Autodesk Fusion 360 part; units mm, degrees
(part 2 of 2)
ref_plane "Plano de trabalho2" through (0, 0, -3) normal (0, 0, 1) x (1, 0, 0) in component "09 / Bicos MIC frontais / dutos a medir"
sketch "Esboço2 (10)" plane through (0, 0, -3) normal (0, 0, 1) x (1, 0, 0) in component "09 / Bicos MIC frontais / dutos a medir"
  circle A0 centre (73, -51) radius 1.8
  circle A1 centre (73, -51) radius 1
extrude "Extrusão2" add sketch "Esboço2 (10)" against normal blind 3 separate body makes body 15 in component "09 / Bicos MIC frontais / dutos a medir"
ref_plane "Plano de trabalho3" through (-90, 0, 0) normal (1, 0, 0) x (0, 1, 0) in component "REF / Vidro 164.28 x 99.17 / area ativa assimetrica"
sketch "Esboço3 (8)" plane through (-90, 0, 0) normal (1, 0, 0) x (0, 0, -1) in component "REF / Vidro 164.28 x 99.17 / area ativa assimetrica"
  line L0 (-0.2, -58) -> (-0.2, -55.065)
  line L1 (-0.2, -55.065) -> (3.2, -53.9603)
  line L2 (3.2, -53.9603) -> (3.2, -58)
  line L3 (3.2, -58) -> (-0.2, -58)
extrude "Nivelar moldura no plano da mesa" cut sketch "Esboço3 (8)" along normal blind 180 bodies 1 in component "01 / Moldura fina / microfones frontais"
sketch "Esboço9 (2)" plane through (0, 0, 0) normal (0, 0, 1) x (1, 0, 0) in component "03 / Tampa traseira / grelha alto-falante + ventilacao"
  point P0 (-10, 0)
  point P1 (10, 0)
  point P2 (0, 20)
ref_plane "Plano de trabalho8" through (-10, 0, -59.0831) normal (0, -0.537781, 0.843084) x (1, 0, 0) in component "03 / Tampa traseira / grelha alto-falante + ventilacao"
ref_plane "Plano de trabalho9" through (-10, -0.0538, -58.9987) normal (0, -0.537781, 0.843084) x (1, 0, 0) in component "03 / Tampa traseira / grelha alto-falante + ventilacao"
sketch "Esboço10" plane through (0, 26.7342, -41.9114) normal (0, -0.537781, 0.843084) x (1, 0, 0) in component "03 / Tampa traseira / grelha alto-falante + ventilacao"
  circle A0 centre (-48, -32.7434) radius 1
  circle A1 centre (-44.8, -32.7434) radius 1
  circle A2 centre (-41.6, -32.7434) radius 1
  circle A3 centre (-38.4, -32.7434) radius 1
  circle A4 centre (-35.2, -32.7434) radius 1
  circle A5 centre (-32, -32.7434) radius 1
  circle A6 centre (-28.8, -32.7434) radius 1
  circle A7 centre (-25.6, -32.7434) radius 1
  circle A8 centre (-22.4, -32.7434) radius 1
  circle A9 centre (-19.2, -32.7434) radius 1
  circle A10 centre (-16, -32.7434) radius 1
  circle A11 centre (-12.8, -32.7434) radius 1
  circle A12 centre (-9.6, -32.7434) radius 1
  circle A13 centre (-6.4, -32.7434) radius 1
  circle A14 centre (-3.2, -32.7434) radius 1
  circle A15 centre (0, -32.7434) radius 1
  circle A16 centre (3.2, -32.7434) radius 1
  circle A17 centre (6.4, -32.7434) radius 1
  circle A18 centre (9.6, -32.7434) radius 1
  circle A19 centre (12.8, -32.7434) radius 1
  circle A20 centre (16, -32.7434) radius 1
  circle A21 centre (19.2, -32.7434) radius 1
  circle A22 centre (22.4, -32.7434) radius 1
  circle A23 centre (25.6, -32.7434) radius 1
  circle A24 centre (28.8, -32.7434) radius 1
  circle A25 centre (32, -32.7434) radius 1
  circle A26 centre (35.2, -32.7434) radius 1
  circle A27 centre (38.4, -32.7434) radius 1
  circle A28 centre (41.6, -32.7434) radius 1
  circle A29 centre (44.8, -32.7434) radius 1
  circle A30 centre (48, -32.7434) radius 1
  circle A31 centre (-48, -29.5434) radius 1
  circle A32 centre (-44.8, -29.5434) radius 1
  circle A33 centre (-41.6, -29.5434) radius 1
  circle A34 centre (-38.4, -29.5434) radius 1
  circle A35 centre (-35.2, -29.5434) radius 1
  circle A36 centre (-32, -29.5434) radius 1
  circle A37 centre (-28.8, -29.5434) radius 1
  circle A38 centre (-25.6, -29.5434) radius 1
  circle A39 centre (-22.4, -29.5434) radius 1
  circle A40 centre (-19.2, -29.5434) radius 1
  circle A41 centre (-16, -29.5434) radius 1
  circle A42 centre (-12.8, -29.5434) radius 1
  circle A43 centre (-9.6, -29.5434) radius 1
  circle A44 centre (-6.4, -29.5434) radius 1
  circle A45 centre (-3.2, -29.5434) radius 1
  circle A46 centre (0, -29.5434) radius 1
  circle A47 centre (3.2, -29.5434) radius 1
  circle A48 centre (6.4, -29.5434) radius 1
  circle A49 centre (9.6, -29.5434) radius 1
  circle A50 centre (12.8, -29.5434) radius 1
  circle A51 centre (16, -29.5434) radius 1
  circle A52 centre (19.2, -29.5434) radius 1
  circle A53 centre (22.4, -29.5434) radius 1
  circle A54 centre (25.6, -29.5434) radius 1
  circle A55 centre (28.8, -29.5434) radius 1
  circle A56 centre (32, -29.5434) radius 1
  circle A57 centre (35.2, -29.5434) radius 1
  circle A58 centre (38.4, -29.5434) radius 1
  circle A59 centre (41.6, -29.5434) radius 1
  circle A60 centre (44.8, -29.5434) radius 1
  circle A61 centre (48, -29.5434) radius 1
  circle A62 centre (-48, -26.3434) radius 1
  circle A63 centre (-44.8, -26.3434) radius 1
  circle A64 centre (-41.6, -26.3434) radius 1
  circle A65 centre (-38.4, -26.3434) radius 1
  circle A66 centre (-35.2, -26.3434) radius 1
  circle A67 centre (-32, -26.3434) radius 1
  circle A68 centre (-28.8, -26.3434) radius 1
  circle A69 centre (-25.6, -26.3434) radius 1
  circle A70 centre (-22.4, -26.3434) radius 1
  circle A71 centre (-19.2, -26.3434) radius 1
  circle A72 centre (-16, -26.3434) radius 1
  circle A73 centre (-12.8, -26.3434) radius 1
  circle A74 centre (-9.6, -26.3434) radius 1
  circle A75 centre (-6.4, -26.3434) radius 1
  circle A76 centre (-3.2, -26.3434) radius 1
  circle A77 centre (0, -26.3434) radius 1
  circle A78 centre (3.2, -26.3434) radius 1
  circle A79 centre (6.4, -26.3434) radius 1
  circle A80 centre (9.6, -26.3434) radius 1
  circle A81 centre (12.8, -26.3434) radius 1
  circle A82 centre (16, -26.3434) radius 1
  circle A83 centre (19.2, -26.3434) radius 1
  circle A84 centre (22.4, -26.3434) radius 1
  circle A85 centre (25.6, -26.3434) radius 1
  circle A86 centre (28.8, -26.3434) radius 1
  circle A87 centre (32, -26.3434) radius 1
  circle A88 centre (35.2, -26.3434) radius 1
  circle A89 centre (38.4, -26.3434) radius 1
  circle A90 centre (41.6, -26.3434) radius 1
  circle A91 centre (44.8, -26.3434) radius 1
  circle A92 centre (48, -26.3434) radius 1
  circle A93 centre (-48, -23.1434) radius 1
  circle A94 centre (-44.8, -23.1434) radius 1
  circle A95 centre (-41.6, -23.1434) radius 1
  circle A96 centre (-38.4, -23.1434) radius 1
  circle A97 centre (-35.2, -23.1434) radius 1
  circle A98 centre (-32, -23.1434) radius 1
  circle A99 centre (-28.8, -23.1434) radius 1
  circle A100 centre (-25.6, -23.1434) radius 1
  circle A101 centre (-22.4, -23.1434) radius 1
  circle A102 centre (-19.2, -23.1434) radius 1
  circle A103 centre (-16, -23.1434) radius 1
  circle A104 centre (-12.8, -23.1434) radius 1
  circle A105 centre (-9.6, -23.1434) radius 1
  circle A106 centre (-6.4, -23.1434) radius 1
  circle A107 centre (-3.2, -23.1434) radius 1
  circle A108 centre (0, -23.1434) radius 1
  circle A109 centre (3.2, -23.1434) radius 1
  circle A110 centre (6.4, -23.1434) radius 1
  circle A111 centre (9.6, -23.1434) radius 1
  circle A112 centre (12.8, -23.1434) radius 1
  circle A113 centre (16, -23.1434) radius 1
  circle A114 centre (19.2, -23.1434) radius 1
  circle A115 centre (22.4, -23.1434) radius 1
  circle A116 centre (25.6, -23.1434) radius 1
  circle A117 centre (28.8, -23.1434) radius 1
  circle A118 centre (32, -23.1434) radius 1
  circle A119 centre (35.2, -23.1434) radius 1
  circle A120 centre (38.4, -23.1434) radius 1
  circle A121 centre (41.6, -23.1434) radius 1
  circle A122 centre (44.8, -23.1434) radius 1
  circle A123 centre (48, -23.1434) radius 1
  circle A124 centre (-48, -19.9434) radius 1
  circle A125 centre (-44.8, -19.9434) radius 1
  circle A126 centre (-41.6, -19.9434) radius 1
  circle A127 centre (-38.4, -19.9434) radius 1
  circle A128 centre (-35.2, -19.9434) radius 1
  circle A129 centre (-32, -19.9434) radius 1
  circle A130 centre (-28.8, -19.9434) radius 1
  circle A131 centre (-25.6, -19.9434) radius 1
  circle A132 centre (-22.4, -19.9434) radius 1
  circle A133 centre (-19.2, -19.9434) radius 1
  circle A134 centre (-16, -19.9434) radius 1
  circle A135 centre (-12.8, -19.9434) radius 1
  circle A136 centre (-9.6, -19.9434) radius 1
  circle A137 centre (-6.4, -19.9434) radius 1
  circle A138 centre (-3.2, -19.9434) radius 1
  circle A139 centre (0, -19.9434) radius 1
  circle A140 centre (3.2, -19.9434) radius 1
  circle A141 centre (6.4, -19.9434) radius 1
  circle A142 centre (9.6, -19.9434) radius 1
  circle A143 centre (12.8, -19.9434) radius 1
  circle A144 centre (16, -19.9434) radius 1
  circle A145 centre (19.2, -19.9434) radius 1
  circle A146 centre (22.4, -19.9434) radius 1
  circle A147 centre (25.6, -19.9434) radius 1
  circle A148 centre (28.8, -19.9434) radius 1
  circle A149 centre (32, -19.9434) radius 1
  circle A150 centre (35.2, -19.9434) radius 1
  circle A151 centre (38.4, -19.9434) radius 1
  circle A152 centre (41.6, -19.9434) radius 1
  circle A153 centre (44.8, -19.9434) radius 1
  circle A154 centre (48, -19.9434) radius 1
  circle A155 centre (-48, -16.7434) radius 1
  circle A156 centre (-44.8, -16.7434) radius 1
  circle A157 centre (-41.6, -16.7434) radius 1
  circle A158 centre (-38.4, -16.7434) radius 1
  circle A159 centre (-35.2, -16.7434) radius 1
  circle A160 centre (-32, -16.7434) radius 1
  circle A161 centre (-28.8, -16.7434) radius 1
  circle A162 centre (-25.6, -16.7434) radius 1
  circle A163 centre (-22.4, -16.7434) radius 1
  circle A164 centre (-19.2, -16.7434) radius 1
  circle A165 centre (-16, -16.7434) radius 1
  circle A166 centre (-12.8, -16.7434) radius 1
  circle A167 centre (-9.6, -16.7434) radius 1
  circle A168 centre (-6.4, -16.7434) radius 1
  circle A169 centre (-3.2, -16.7434) radius 1
  circle A170 centre (0, -16.7434) radius 1
  circle A171 centre (3.2, -16.7434) radius 1
  circle A172 centre (6.4, -16.7434) radius 1
  circle A173 centre (9.6, -16.7434) radius 1
  circle A174 centre (12.8, -16.7434) radius 1
  circle A175 centre (16, -16.7434) radius 1
  circle A176 centre (19.2, -16.7434) radius 1
  circle A177 centre (22.4, -16.7434) radius 1
  circle A178 centre (25.6, -16.7434) radius 1
  circle A179 centre (28.8, -16.7434) radius 1
  circle A180 centre (32, -16.7434) radius 1
  circle A181 centre (35.2, -16.7434) radius 1
  circle A182 centre (38.4, -16.7434) radius 1
  circle A183 centre (41.6, -16.7434) radius 1
  circle A184 centre (44.8, -16.7434) radius 1
  circle A185 centre (48, -16.7434) radius 1
  circle A186 centre (-48, -13.5434) radius 1
  circle A187 centre (-44.8, -13.5434) radius 1
  circle A188 centre (-41.6, -13.5434) radius 1
  circle A189 centre (-38.4, -13.5434) radius 1
  circle A190 centre (-35.2, -13.5434) radius 1
  circle A191 centre (-32, -13.5434) radius 1
  circle A192 centre (-28.8, -13.5434) radius 1
  circle A193 centre (-25.6, -13.5434) radius 1
  circle A194 centre (-22.4, -13.5434) radius 1
  circle A195 centre (-19.2, -13.5434) radius 1
  circle A196 centre (-16, -13.5434) radius 1
  circle A197 centre (-12.8, -13.5434) radius 1
  circle A198 centre (-9.6, -13.5434) radius 1
  circle A199 centre (-6.4, -13.5434) radius 1
  circle A200 centre (-3.2, -13.5434) radius 1
  circle A201 centre (0, -13.5434) radius 1
  circle A202 centre (3.2, -13.5434) radius 1
  circle A203 centre (6.4, -13.5434) radius 1
  circle A204 centre (9.6, -13.5434) radius 1
  circle A205 centre (12.8, -13.5434) radius 1
  circle A206 centre (16, -13.5434) radius 1
  circle A207 centre (19.2, -13.5434) radius 1
  circle A208 centre (22.4, -13.5434) radius 1
  circle A209 centre (25.6, -13.5434) radius 1
  circle A210 centre (28.8, -13.5434) radius 1
  circle A211 centre (32, -13.5434) radius 1
  circle A212 centre (35.2, -13.5434) radius 1
  circle A213 centre (38.4, -13.5434) radius 1
  circle A214 centre (41.6, -13.5434) radius 1
  circle A215 centre (44.8, -13.5434) radius 1
  circle A216 centre (48, -13.5434) radius 1
  circle A217 centre (-48, -10.3434) radius 1
  circle A218 centre (-44.8, -10.3434) radius 1
  circle A219 centre (-41.6, -10.3434) radius 1
  circle A220 centre (-38.4, -10.3434) radius 1
  circle A221 centre (-35.2, -10.3434) radius 1
  circle A222 centre (-32, -10.3434) radius 1
  circle A223 centre (-28.8, -10.3434) radius 1
  circle A224 centre (-25.6, -10.3434) radius 1
  circle A225 centre (-22.4, -10.3434) radius 1
  circle A226 centre (-19.2, -10.3434) radius 1
  circle A227 centre (-16, -10.3434) radius 1
  circle A228 centre (-12.8, -10.3434) radius 1
  circle A229 centre (-9.6, -10.3434) radius 1
  circle A230 centre (-6.4, -10.3434) radius 1
  circle A231 centre (-3.2, -10.3434) radius 1
  circle A232 centre (0, -10.3434) radius 1
  circle A233 centre (3.2, -10.3434) radius 1
  circle A234 centre (6.4, -10.3434) radius 1
  circle A235 centre (9.6, -10.3434) radius 1
  circle A236 centre (12.8, -10.3434) radius 1
  circle A237 centre (16, -10.3434) radius 1
  circle A238 centre (19.2, -10.3434) radius 1
  circle A239 centre (22.4, -10.3434) radius 1
  circle A240 centre (25.6, -10.3434) radius 1
  circle A241 centre (28.8, -10.3434) radius 1
  circle A242 centre (32, -10.3434) radius 1
  circle A243 centre (35.2, -10.3434) radius 1
  circle A244 centre (38.4, -10.3434) radius 1
  circle A245 centre (41.6, -10.3434) radius 1
  circle A246 centre (44.8, -10.3434) radius 1
  circle A247 centre (48, -10.3434) radius 1
  circle A248 centre (-48, -7.1434) radius 1
  circle A249 centre (-44.8, -7.1434) radius 1
  circle A250 centre (-41.6, -7.1434) radius 1
  circle A251 centre (-38.4, -7.1434) radius 1
  circle A252 centre (-35.2, -7.1434) radius 1
  circle A253 centre (-32, -7.1434) radius 1
  circle A254 centre (-28.8, -7.1434) radius 1
  circle A255 centre (-25.6, -7.1434) radius 1
  circle A256 centre (-22.4, -7.1434) radius 1
  circle A257 centre (-19.2, -7.1434) radius 1
  circle A258 centre (-16, -7.1434) radius 1
  circle A259 centre (-12.8, -7.1434) radius 1
  circle A260 centre (-9.6, -7.1434) radius 1
  circle A261 centre (-6.4, -7.1434) radius 1
  circle A262 centre (-3.2, -7.1434) radius 1
  circle A263 centre (0, -7.1434) radius 1
  circle A264 centre (3.2, -7.1434) radius 1
  circle A265 centre (6.4, -7.1434) radius 1
  circle A266 centre (9.6, -7.1434) radius 1
  circle A267 centre (12.8, -7.1434) radius 1
  circle A268 centre (16, -7.1434) radius 1
  circle A269 centre (19.2, -7.1434) radius 1
  circle A270 centre (22.4, -7.1434) radius 1
  circle A271 centre (25.6, -7.1434) radius 1
  circle A272 centre (28.8, -7.1434) radius 1
  circle A273 centre (32, -7.1434) radius 1
  circle A274 centre (35.2, -7.1434) radius 1
  circle A275 centre (38.4, -7.1434) radius 1
  circle A276 centre (41.6, -7.1434) radius 1
  circle A277 centre (44.8, -7.1434) radius 1
  circle A278 centre (48, -7.1434) radius 1
  circle A279 centre (-48, -3.9434) radius 1
  circle A280 centre (-44.8, -3.9434) radius 1
  circle A281 centre (-41.6, -3.9434) radius 1
  circle A282 centre (-38.4, -3.9434) radius 1
  circle A283 centre (-35.2, -3.9434) radius 1
  circle A284 centre (-32, -3.9434) radius 1
  circle A285 centre (-28.8, -3.9434) radius 1
  circle A286 centre (-25.6, -3.9434) radius 1
  circle A287 centre (-22.4, -3.9434) radius 1
  circle A288 centre (-19.2, -3.9434) radius 1
  circle A289 centre (-16, -3.9434) radius 1
  circle A290 centre (-12.8, -3.9434) radius 1
  circle A291 centre (-9.6, -3.9434) radius 1
  circle A292 centre (-6.4, -3.9434) radius 1
  circle A293 centre (-3.2, -3.9434) radius 1
  circle A294 centre (0, -3.9434) radius 1
  circle A295 centre (3.2, -3.9434) radius 1
  circle A296 centre (6.4, -3.9434) radius 1
  circle A297 centre (9.6, -3.9434) radius 1
  circle A298 centre (12.8, -3.9434) radius 1
  circle A299 centre (16, -3.9434) radius 1
  circle A300 centre (19.2, -3.9434) radius 1
  circle A301 centre (22.4, -3.9434) radius 1
  circle A302 centre (25.6, -3.9434) radius 1
  circle A303 centre (28.8, -3.9434) radius 1
  circle A304 centre (32, -3.9434) radius 1
  circle A305 centre (35.2, -3.9434) radius 1
  circle A306 centre (38.4, -3.9434) radius 1
  circle A307 centre (41.6, -3.9434) radius 1
  circle A308 centre (44.8, -3.9434) radius 1
  circle A309 centre (48, -3.9434) radius 1
  circle A310 centre (-48, -0.7434) radius 1
  circle A311 centre (-44.8, -0.7434) radius 1
  circle A312 centre (-41.6, -0.7434) radius 1
  circle A313 centre (-38.4, -0.7434) radius 1
  circle A314 centre (-35.2, -0.7434) radius 1
  circle A315 centre (-32, -0.7434) radius 1
  circle A316 centre (-28.8, -0.7434) radius 1
  circle A317 centre (-25.6, -0.7434) radius 1
  circle A318 centre (-22.4, -0.7434) radius 1
  circle A319 centre (-19.2, -0.7434) radius 1
  circle A320 centre (-16, -0.7434) radius 1
  circle A321 centre (-12.8, -0.7434) radius 1
  circle A322 centre (-9.6, -0.7434) radius 1
  circle A323 centre (-6.4, -0.7434) radius 1
  circle A324 centre (-3.2, -0.7434) radius 1
  circle A325 centre (0, -0.7434) radius 1
  circle A326 centre (3.2, -0.7434) radius 1
  circle A327 centre (6.4, -0.7434) radius 1
  circle A328 centre (9.6, -0.7434) radius 1
  circle A329 centre (12.8, -0.7434) radius 1
  circle A330 centre (16, -0.7434) radius 1
  circle A331 centre (19.2, -0.7434) radius 1
  circle A332 centre (22.4, -0.7434) radius 1
  circle A333 centre (25.6, -0.7434) radius 1
  circle A334 centre (28.8, -0.7434) radius 1
  circle A335 centre (32, -0.7434) radius 1
  circle A336 centre (35.2, -0.7434) radius 1
  circle A337 centre (38.4, -0.7434) radius 1
  circle A338 centre (41.6, -0.7434) radius 1
  circle A339 centre (44.8, -0.7434) radius 1
  circle A340 centre (48, -0.7434) radius 1
extrude "341 perfuracoes de audio traseiras" cut sketch "Esboço10" against normal blind 2.7 bodies 5 in component "03 / Tampa traseira / grelha alto-falante + ventilacao"
sketch "Esboço1 (11)" plane through (0, 0, 0) normal (0, 0, 1) x (1, 0, 0) in component "REF / Alto-falante TRASEIRO / 100 x 45 x 20 medido pelo usuario"
  point P0 (-10, 0)
  point P1 (10, 0)
  point P2 (0, 20)
ref_plane "Plano de trabalho1" through (-10, 0, -59.0831) normal (0, -0.537781, 0.843084) x (1, 0, 0) in component "REF / Alto-falante TRASEIRO / 100 x 45 x 20 medido pelo usuario"
ref_plane "Plano de trabalho2" through (-10, -2.6889, -54.8676) normal (0, -0.537781, 0.843084) x (1, 0, 0) in component "REF / Alto-falante TRASEIRO / 100 x 45 x 20 medido pelo usuario"
sketch "Esboço2 (11)" plane through (0, 24.0991, -37.7803) normal (0, -0.537781, 0.843084) x (1, 0, 0) in component "REF / Alto-falante TRASEIRO / 100 x 45 x 20 medido pelo usuario"
  line L0 (-47, -39.2434) -> (47, -39.2434)
  line L1 (50, -36.2434) -> (50, 2.7566)
  line L2 (47, 5.7566) -> (-47, 5.7566)
  line L3 (-50, 2.7566) -> (-50, -36.2434)
  arc A0 (47, -39.2434) -> (50, -36.2434) centre (47, -36.2434) ccw
  arc A1 (50, 2.7566) -> (47, 5.7566) centre (47, 2.7566) ccw
  arc A2 (-47, 5.7566) -> (-50, 2.7566) centre (-47, 2.7566) ccw
  arc A3 (-50, -36.2434) -> (-47, -39.2434) centre (-47, -36.2434) ccw
extrude "Alto-falante 100 x 45 x 20" add sketch "Esboço2 (11)" along normal blind 20 separate body makes body 16 in component "REF / Alto-falante TRASEIRO / 100 x 45 x 20 medido pelo usuario"
sketch "Esboço1 (12)" plane through (0, 0, 0) normal (0, 0, 1) x (1, 0, 0) in component "05 / Berco traseiro / alojamento 104 x 49 x 24"
  point P0 (-10, 0)
  point P1 (10, 0)
  point P2 (0, 20)
ref_plane "Plano de trabalho1" through (-10, 0, -59.0831) normal (0, -0.537781, 0.843084) x (1, 0, 0) in component "05 / Berco traseiro / alojamento 104 x 49 x 24"
ref_plane "Plano de trabalho2" through (-10, -1.6133, -56.5538) normal (0, -0.537781, 0.843084) x (1, 0, 0) in component "05 / Berco traseiro / alojamento 104 x 49 x 24"
sketch "Esboço2 (12)" plane through (0, 25.1746, -39.4665) normal (0, -0.537781, 0.843084) x (1, 0, 0) in component "05 / Berco traseiro / alojamento 104 x 49 x 24"
  line L0 (-50, -43.2434) -> (50, -43.2434)
  line L1 (54, -39.2434) -> (54, 5.7566)
  line L2 (50, 9.7566) -> (-50, 9.7566)
  line L3 (-54, 5.7566) -> (-54, -39.2434)
  arc A0 (50, -43.2434) -> (54, -39.2434) centre (50, -39.2434) ccw
  arc A1 (54, 5.7566) -> (50, 9.7566) centre (50, 5.7566) ccw
  arc A2 (-50, 9.7566) -> (-54, 5.7566) centre (-50, 5.7566) ccw
  arc A3 (-54, -39.2434) -> (-50, -43.2434) centre (-50, -39.2434) ccw
  line L4 (-50, -41.2434) -> (50, -41.2434)
  line L5 (52, -39.2434) -> (52, 5.7566)
  line L6 (50, 7.7566) -> (-50, 7.7566)
  line L7 (-52, 5.7566) -> (-52, -39.2434)
  arc A4 (50, -41.2434) -> (52, -39.2434) centre (50, -39.2434) ccw
  arc A5 (52, 5.7566) -> (50, 7.7566) centre (50, 5.7566) ccw
  arc A6 (-50, 7.7566) -> (-52, 5.7566) centre (-50, 5.7566) ccw
  arc A7 (-52, -39.2434) -> (-50, -41.2434) centre (-50, -39.2434) ccw
extrude "Berco para alto-falante medido" add sketch "Esboço2 (12)" along normal blind 24 separate body makes body 17 in component "05 / Berco traseiro / alojamento 104 x 49 x 24"
sketch "Esboço3 (9)" plane through (0, 0, 0) normal (0, 0, 1) x (1, 0, 0) in component "05 / Berco traseiro / alojamento 104 x 49 x 24"
  point P0 (-10, 0)
  point P1 (10, 0)
  point P2 (0, 20)
ref_plane "Plano de trabalho3" through (-10, 0, -59.0831) normal (0, -0.537781, 0.843084) x (1, 0, 0) in component "05 / Berco traseiro / alojamento 104 x 49 x 24"
ref_plane "Plano de trabalho4" through (-10, -1.6133, -56.5538) normal (0, -0.537781, 0.843084) x (1, 0, 0) in component "05 / Berco traseiro / alojamento 104 x 49 x 24"
sketch "Esboço4 (6)" plane through (0, 25.1746, -39.4665) normal (0, -0.537781, 0.843084) x (1, 0, 0) in component "05 / Berco traseiro / alojamento 104 x 49 x 24"
  line L0 (-50, -43.2434) -> (50, -43.2434)
  line L1 (54, -39.2434) -> (54, 5.7566)
  line L2 (50, 9.7566) -> (-50, 9.7566)
  line L3 (-54, 5.7566) -> (-54, -39.2434)
  arc A0 (50, -43.2434) -> (54, -39.2434) centre (50, -39.2434) ccw
  arc A1 (54, 5.7566) -> (50, 9.7566) centre (50, 5.7566) ccw
  arc A2 (-50, 9.7566) -> (-54, 5.7566) centre (-50, 5.7566) ccw
  arc A3 (-54, -39.2434) -> (-50, -43.2434) centre (-50, -39.2434) ccw
  line L4 (-45, -36.2434) -> (45, -36.2434)
  line L5 (47, -34.2434) -> (47, 0.7566)
  line L6 (45, 2.7566) -> (-45, 2.7566)
  line L7 (-47, 0.7566) -> (-47, -34.2434)
  arc A4 (45, -36.2434) -> (47, -34.2434) centre (45, -34.2434) ccw
  arc A5 (47, 0.7566) -> (45, 2.7566) centre (45, 0.7566) ccw
  arc A6 (-45, 2.7566) -> (-47, 0.7566) centre (-45, 0.7566) ccw
  arc A7 (-47, -34.2434) -> (-45, -36.2434) centre (-45, -34.2434) ccw
extrude "Assento perifÃ©rico / vedacao compressÃ­vel" add sketch "Esboço4 (6)" along normal blind 2 bodies 17 in component "05 / Berco traseiro / alojamento 104 x 49 x 24"
sketch "Esboço5 (6)" plane through (0, 0, 0) normal (0, 0, 1) x (1, 0, 0) in component "05 / Berco traseiro / alojamento 104 x 49 x 24"
  point P0 (-10, 0)
  point P1 (10, 0)
  point P2 (0, 20)
ref_plane "Plano de trabalho5" through (-10, 0, -59.0831) normal (0, -0.537781, 0.843084) x (1, 0, 0) in component "05 / Berco traseiro / alojamento 104 x 49 x 24"
sketch "Esboço6 (4)" plane through (0, 26.788, -41.9957) normal (0, -0.537781, 0.843084) x (1, 0, 0) in component "05 / Berco traseiro / alojamento 104 x 49 x 24"
  line L0 (-57, -39.7434) -> (-53, -39.7434)
  line L1 (-51, -37.7434) -> (-51, -27.7434)
  line L2 (-53, -25.7434) -> (-57, -25.7434)
  line L3 (-59, -27.7434) -> (-59, -37.7434)
  arc A0 (-53, -39.7434) -> (-51, -37.7434) centre (-53, -37.7434) ccw
  arc A1 (-51, -27.7434) -> (-53, -25.7434) centre (-53, -27.7434) ccw
  arc A2 (-57, -25.7434) -> (-59, -27.7434) centre (-57, -27.7434) ccw
  arc A3 (-59, -37.7434) -> (-57, -39.7434) centre (-57, -37.7434) ccw
  line L4 (-57, -7.7434) -> (-53, -7.7434)
  line L5 (-51, -5.7434) -> (-51, 4.2566)
  line L6 (-53, 6.2566) -> (-57, 6.2566)
  line L7 (-59, 4.2566) -> (-59, -5.7434)
  arc A4 (-53, -7.7434) -> (-51, -5.7434) centre (-53, -5.7434) ccw
  arc A5 (-51, 4.2566) -> (-53, 6.2566) centre (-53, 4.2566) ccw
  arc A6 (-57, 6.2566) -> (-59, 4.2566) centre (-57, 4.2566) ccw
  arc A7 (-59, -5.7434) -> (-57, -7.7434) centre (-57, -5.7434) ccw
  line L8 (53, -39.7434) -> (57, -39.7434)
  line L9 (59, -37.7434) -> (59, -27.7434)
  line L10 (57, -25.7434) -> (53, -25.7434)
  line L11 (51, -27.7434) -> (51, -37.7434)
  arc A8 (57, -39.7434) -> (59, -37.7434) centre (57, -37.7434) ccw
  arc A9 (59, -27.7434) -> (57, -25.7434) centre (57, -27.7434) ccw
  arc A10 (53, -25.7434) -> (51, -27.7434) centre (53, -27.7434) ccw
  arc A11 (51, -37.7434) -> (53, -39.7434) centre (53, -37.7434) ccw
  line L12 (53, -7.7434) -> (57, -7.7434)
  line L13 (59, -5.7434) -> (59, 4.2566)
  line L14 (57, 6.2566) -> (53, 6.2566)
  line L15 (51, 4.2566) -> (51, -5.7434)
  arc A12 (57, -7.7434) -> (59, -5.7434) centre (57, -5.7434) ccw
  arc A13 (59, 4.2566) -> (57, 6.2566) centre (57, 4.2566) ccw
  arc A14 (53, 6.2566) -> (51, 4.2566) centre (53, 4.2566) ccw
  arc A15 (51, -5.7434) -> (53, -7.7434) centre (53, -5.7434) ccw
extrude "4 abas fixacao berco" add sketch "Esboço6 (4)" along normal blind 5 bodies 17 in component "05 / Berco traseiro / alojamento 104 x 49 x 24"
sketch "Esboço7 (3)" plane through (0, 0, 0) normal (0, 0, 1) x (1, 0, 0) in component "05 / Berco traseiro / alojamento 104 x 49 x 24"
  point P0 (-10, 0)
  point P1 (10, 0)
  point P2 (0, 20)
ref_plane "Plano de trabalho6" through (-10, 0, -59.0831) normal (0, -0.537781, 0.843084) x (1, 0, 0) in component "05 / Berco traseiro / alojamento 104 x 49 x 24"
ref_plane "Plano de trabalho7" through (-10, -2.7427, -54.7833) normal (0, -0.537781, 0.843084) x (1, 0, 0) in component "05 / Berco traseiro / alojamento 104 x 49 x 24"
sketch "Esboço8 (3)" plane through (0, 24.0453, -37.696) normal (0, -0.537781, 0.843084) x (1, 0, 0) in component "05 / Berco traseiro / alojamento 104 x 49 x 24"
  circle A0 centre (-56, -32.7434) radius 1.3
  circle A1 centre (-56, -0.7434) radius 1.3
  circle A2 centre (56, -32.7434) radius 1.3
  circle A3 centre (56, -0.7434) radius 1.3
extrude "4 pilotos M3 no berco / ajustar inserto" cut sketch "Esboço8 (3)" against normal blind 5.3 bodies 5 in component "03 / Tampa traseira / grelha alto-falante + ventilacao"
extrude "Extrusão4" cut sketch "Esboço8 (3)" against normal blind 5.3 bodies 17 in component "05 / Berco traseiro / alojamento 104 x 49 x 24"
sketch "Esboço11" plane through (0, 0, 0) normal (0, 0, 1) x (1, 0, 0) in component "03 / Tampa traseira / grelha alto-falante + ventilacao"
  point P0 (-10, 0)
  point P1 (10, 0)
  point P2 (0, 20)
ref_plane "Plano de trabalho10" through (-10, 0, -59.0831) normal (0, -0.537781, 0.843084) x (1, 0, 0) in component "03 / Tampa traseira / grelha alto-falante + ventilacao"
ref_plane "Plano de trabalho11" through (-10, -0.0538, -58.9987) normal (0, -0.537781, 0.843084) x (1, 0, 0) in component "03 / Tampa traseira / grelha alto-falante + ventilacao"
sketch "Esboço12" plane through (0, 26.7342, -41.9114) normal (0, -0.537781, 0.843084) x (1, 0, 0) in component "03 / Tampa traseira / grelha alto-falante + ventilacao"
  circle A0 centre (-56, -32.7434) radius 1.6
  circle A1 centre (-56, -0.7434) radius 1.6
  circle A2 centre (56, -32.7434) radius 1.6
  circle A3 centre (56, -0.7434) radius 1.6
extrude "4 passagens M3 / fixacao berco" cut sketch "Esboço12" against normal blind 2.7 bodies 5 in component "03 / Tampa traseira / grelha alto-falante + ventilacao"
extrude "Extrusão5'" cut sketch "Esboço12" against normal blind 2.7 bodies 17 in component "05 / Berco traseiro / alojamento 104 x 49 x 24"
component "REF / Vidro 164.28 x 99.17 / area ativa assimetrica" placed x (1, 0, 0) y (0, 0.309017, 0.951057) z (0, -0.951057, 0.309017) at (0, 16.9959, 52.3081)
component "02 / Corpo em cunha / apoio direto na mesa" placed x (1, 0, 0) y (0, 0.309017, 0.951057) z (0, -0.951057, 0.309017) at (0, 16.9959, 52.3081)
component "03 / Tampa traseira / grelha alto-falante + ventilacao" placed x (1, 0, 0) y (0, 0.309017, 0.951057) z (0, -0.951057, 0.309017) at (0, 16.9959, 52.3081)
component "01 / Moldura fina / microfones frontais" placed x (1, 0, 0) y (0, 0.309017, 0.951057) z (0, -0.951057, 0.309017) at (0, 16.9959, 52.3081)
component "REF / PCB 164 x 97 / pitch furos 156 x 89" placed x (1, 0, 0) y (0, 0.309017, 0.951057) z (0, -0.951057, 0.309017) at (0, 16.9959, 52.3081)
component "04 / Apoios PCB / distancias da foto" placed x (1, 0, 0) y (0, 0.309017, 0.951057) z (0, -0.951057, 0.309017) at (0, 16.9959, 52.3081)
component "06 / Volume + e - / teclas no topo" placed x (1, 0, 0) y (0, 0.309017, 0.951057) z (0, -0.951057, 0.309017) at (0, 16.9959, 52.3081)
component "07 / Suporte dos switches volume / eletrica pendente" placed x (1, 0, 0) y (0, 0.309017, 0.951057) z (0, -0.951057, 0.309017) at (0, 16.9959, 52.3081)
component "08 / Cursor lateral ON OFF / aciona chave da placa" placed x (1, 0, 0) y (0, 0.309017, 0.951057) z (0, -0.951057, 0.309017) at (0, 16.9959, 52.3081)
component "09 / Bicos MIC frontais / dutos a medir" placed x (1, 0, 0) y (0, 0.309017, 0.951057) z (0, -0.951057, 0.309017) at (0, 16.9959, 52.3081)
component "REF / Alto-falante TRASEIRO / 100 x 45 x 20 medido pelo usuario" placed x (1, 0, 0) y (0, 0.309017, 0.951057) z (0, -0.951057, 0.309017) at (0, 16.9959, 52.3081)
component "05 / Berco traseiro / alojamento 104 x 49 x 24" placed x (1, 0, 0) y (0, 0.309017, 0.951057) z (0, -0.951057, 0.309017) at (0, 16.9959, 52.3081)
equation "wall = 2.4 mm" comment "Parede da carcaca"
equation "bezel = 3 mm" comment "Moldura frontal"
equation "rear_cover = 2.4 mm" comment "Tampa traseira"
equation "pcb_holes_x = 156 mm" comment "Entre furos da foto"
equation "pcb_holes_y = 89 mm" comment "Entre furos; PCB total 97 mm"
equation "d6 = -bezel"
equation "d30 = wall"
equation "d52 = -rear_cover"
equation "speaker_width_ref = 100 mm" comment "Medido pelo usuario"
equation "speaker_height_ref = 45 mm" comment "Medido pelo usuario"
equation "speaker_depth = 20 mm" comment "Usuario informou 2 cm"
equation "speaker_clearance_ref = 2 mm" comment "Folga por lado do berco"
equation "d201 = speaker_depth"
